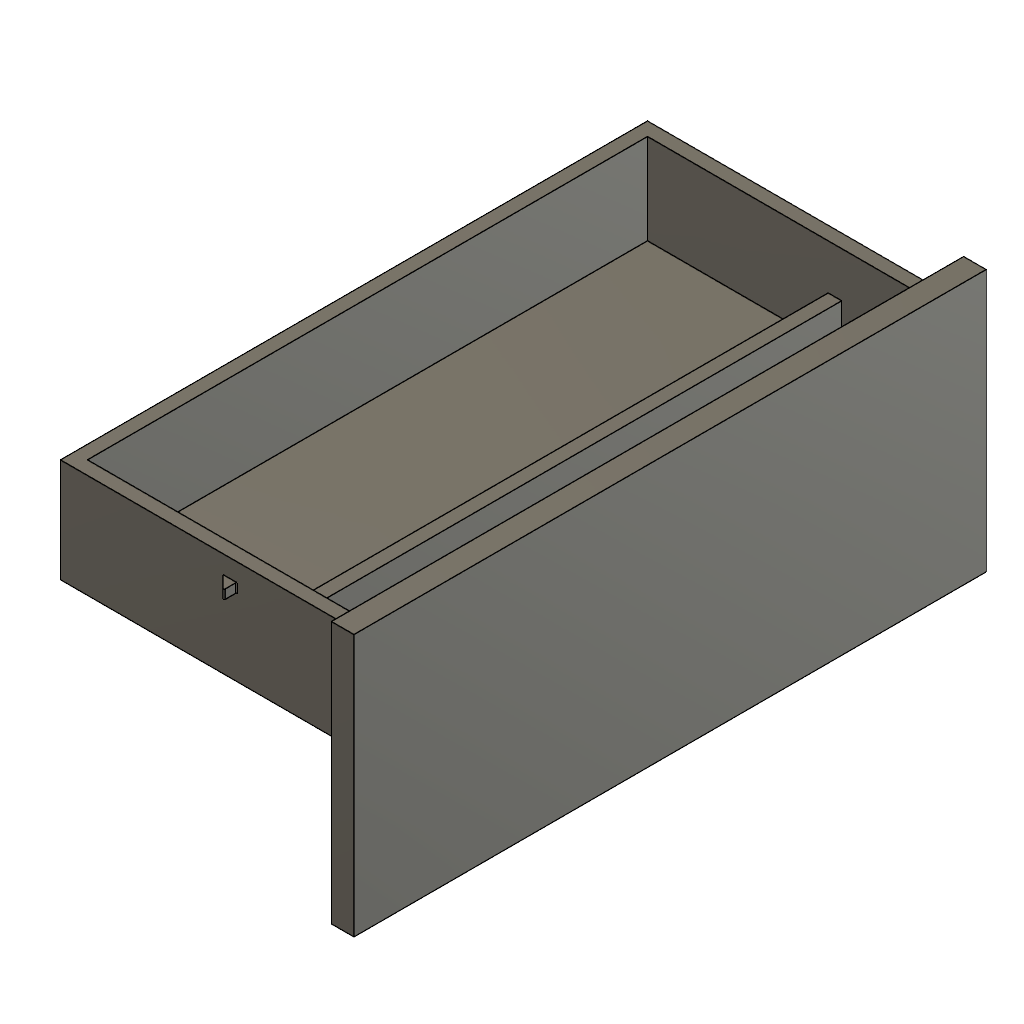
BALANCIN_V4 (Autodesk Fusion 360 archive; units mm, degrees)
design "CAJA BATERIA"
part number: 2026-09-12-01-05-41-271
Autodesk Fusion 360 part; units mm, degrees
sketch "Boceto9" plane through (0, 0, 0) normal (1, 0, 0) x (0, 0, -1)
  line L0 (0, 0) -> (130, 0)
  line L1 (130, 0) -> (130, 3)
  line L2 (130, 3) -> (0, 3)
  line L3 (0, 3) -> (0, 0)
  dimension "d48" = 130
  dimension "d49" = 3
  constraint horizontal L0
  constraint vertical L1
  constraint horizontal L2
  constraint vertical L3
  constraint coincident L0.start L3.end
  measures "d48" distance of L0.start L0.end
  measures "d49" distance of L0.start L2.end
extrude "Extruir9" add sketch "Boceto9" against normal blind 65
sketch "Boceto11" plane through (0, 3, 0) normal (0, 1, 0) x (-1, 0, 0)
  line L0 (0, -130) -> (65, -130)
  line L1 (65, -130) -> (65, 0)
  line L2 (65, 0) -> (0, 0)
  line L3 (0, -130) -> (65, -130)
  line L4 (65, -130) -> (65, -127)
  line L5 (65, -127) -> (0, -127)
  line L6 (0, -127) -> (0, -130)
  line L7 (65, -130) -> (62, -130)
  line L8 (62, -130) -> (62, 0)
  line L9 (62, 0) -> (65, 0)
  line L10 (65, 0) -> (65, -130)
  line L11 (0, 0) -> (65, 0)
  line L12 (65, 0) -> (65, -3)
  line L13 (65, -3) -> (0, -3)
  line L14 (0, -3) -> (0, 0)
  line L15 (0, 0) -> (0, -130)
  line L16 (0, 0) -> (-5, 0)
  line L17 (-5, 0) -> (-5, -3)
  line L18 (-5, -3) -> (0, -3)
  line L19 (0, -3) -> (0, 0)
  line L20 (0, -130) -> (-5, -130)
  line L21 (-5, -130) -> (-5, -127)
  line L22 (-5, -127) -> (0, -127)
  line L23 (0, -127) -> (0, -130)
  dimension "d59" = 3
  dimension "d60" = 3
  dimension "d61" = 3
  dimension "d93" = 5
  dimension "d94" = 3
  dimension "d95" = 5
  dimension "d96" = 3
  constraint horizontal L3
  constraint vertical L4
  constraint horizontal L5
  constraint vertical L6
  constraint coincident L0.start L3.start
  constraint horizontal L7
  constraint vertical L8
  constraint horizontal L9
  constraint vertical L10
  constraint horizontal L11
  constraint vertical L12
  constraint horizontal L13
  constraint vertical L14
  constraint coincident L2.end L11.start
  constraint horizontal L16
  constraint vertical L17
  constraint horizontal L18
  constraint vertical L19
  constraint horizontal L20
  constraint vertical L21
  constraint horizontal L22
  constraint vertical L23
  measures "d59" distance of L0.start L5.end
  measures "d60" distance of L0.end L7.end
  measures "d61" distance of L2.end L13.end
  measures "d93" distance of L2.end L16.end
  measures "d94" distance of L2.end L13.end
  measures "d95" distance of L0.start L20.end
  measures "d96" distance of L0.start L5.end
extrude "Extruir11" add sketch "Boceto11" along normal blind 20 contours L0 L3 L5 L6 L8 L15 L23 | L6 L15 L20 L21 L22 L23 | L0 L1 L3 L4 L5 L7 L8 L10 | L1 L5 L8 L10 L13 | L2 L8 L11 L13 L14 L15 L19 | L14 L15 L16 L17 L18 L19 | L1 L2 L8 L9 L10 L11 L12 L13
sketch "Boceto12" plane through (0, 3, 0) normal (0, 1, 0) x (-1, 0, 0)
  line L0 (62, -3) -> (0, -3)
  line L1 (0, -127) -> (62, -127)
  line L2 (62, -127) -> (62, -3)
  line L3 (62, -127) -> (22, -127)
  line L4 (22, -127) -> (19, -127)
  line L5 (19, -127) -> (19, -7)
  line L6 (19, -7) -> (22, -7)
  line L7 (22, -7) -> (22, -127)
  line L8 (19, -7) -> (39, -7)
  line L9 (39, -7) -> (39, -3)
  line L10 (39, -3) -> (19, -3)
  line L11 (19, -3) -> (19, -7)
  line L12 (0, -3) -> (0, -127)
  dimension "d68" = 40
  dimension "d69" = 3
  dimension "d70" = 120
  dimension "d71" = 20
  constraint coincident L1.end L2.start
  constraint perpendicular L2 L3
  constraint horizontal L4
  constraint vertical L5
  constraint horizontal L6
  constraint vertical L7
  constraint horizontal L8
  constraint vertical L9
  constraint horizontal L10
  constraint vertical L11
  measures "d68" distance of L1.end L3.end
  measures "d69" distance of L3.end L4.end
  measures "d70" distance of L3.end L6.end
  measures "d71" distance of L5.end L8.end
extrude "Extruir12" add sketch "Boceto12" along normal blind 10 contours L0 L6 L8 L9 L10 L11 | L1 L4 L5 L6 L7 L8
sketch "Boceto13" plane through (0, 23, 0) normal (0, 1, 0) x (-1, 0, 0)
  line L0 (62, -127) -> (-5, -127)
  line L1 (-5, -130) -> (65, -130)
  line L2 (65, -130) -> (65, 0)
  line L3 (65, 0) -> (-5, 0)
  line L4 (-5, -3) -> (62, -3)
  line L5 (62, -3) -> (62, -127)
  line L6 (-5, 0) -> (25.8, 0)
  line L7 (-5, -130) -> (25.8, -130)
  line L8 (26, 0.2) -> (26, 2.5172)
  line L9 (26, 0) -> (29, 0)
  line L10 (29, 0) -> (26.3414, 2.6586)
  arc A0 (26.3414, 2.6586) -> (26, 2.5172) centre (26.2, 2.5172) ccw
  arc A1 (25.8, 0) -> (26, 0.2) centre (25.8, 0.2) ccw
  line L11 (26, -130.2) -> (26, -132.5172)
  line L12 (26, -130) -> (29, -130)
  line L13 (29, -130) -> (26.3414, -132.6586)
  arc A2 (26, -132.5172) -> (26.3414, -132.6586) centre (26.2, -132.5172) ccw
  arc A3 (26, -130.2) -> (25.8, -130) centre (25.8, -130.2) ccw
  line L14 (-5, 0) -> (-5, -3)
  line L15 (-5, -127) -> (-5, -130)
  point P0 (26, 3)
  point P1 (26, -133)
  dimension "d85" = 31
  dimension "d86" = 3
  dimension "d87" = 3
  dimension "d88" = 0.2
  dimension "d89" = 31
  dimension "d90" = 3
  dimension "d91" = 3
  dimension "d92" = 0.2
  constraint coincident L3.end L6.start
  constraint coincident L1.start L7.start
  constraint perpendicular L3 L8
  constraint perpendicular L8 L9
  constraint coincident P0 L8
  constraint coincident P0 L10
  constraint tangent L8 A0
  constraint tangent L10 A0
  constraint coincident L6 L9.start
  constraint coincident L9.start L8
  constraint tangent L6 A1
  constraint tangent L8 A1
  constraint equal A0 A1
  constraint perpendicular L7 L11
  constraint perpendicular L11 L12
  constraint coincident P1 L11
  constraint coincident P1 L13
  constraint tangent L11 A2
  constraint tangent L13 A2
  constraint coincident L7 L12.start
  constraint coincident L12.start L11
  constraint tangent L7 A3
  constraint tangent L11 A3
  constraint equal A2 A3
  measures "d85" distance of L3.end L9.start
  measures "d86" distance of L9.start P0
  measures "d87" distance of L9.start L9.end
  measures "d88" radius of A0
  measures "d89" distance of L1.start L12.start
  measures "d90" distance of L12.start P1
  measures "d91" distance of L12.start L12.end
  measures "d92" radius of A2
extrude "Extruir13" add sketch "Boceto13" against normal blind 2 from surface at -4
sketch "Boceto10" plane through (0, 0, 0) normal (1, 0, 0) x (0, 0, -1)
  line L0 (0, 0) -> (-5, 0)
  line L1 (-5, 0) -> (-5, 27)
  line L2 (-5, 27) -> (135, 27)
  line L3 (135, 27) -> (135, -31)
  line L4 (135, -31) -> (-5, -31)
  line L5 (-5, -31) -> (-5, 27)
  line L6 (0, 0) -> (0, 3)
  line L7 (0, 3) -> (3, 3)
  line L8 (3, 3) -> (3, 23)
  line L9 (3, 23) -> (0, 23)
  line L10 (0, 23) -> (0, 3)
  line L11 (130, 3) -> (127, 3)
  line L12 (127, 3) -> (127, 23)
  line L13 (127, 23) -> (130, 23)
  line L14 (130, 23) -> (130, 3)
  dimension "d64" = 5
  dimension "d65" = 27
  dimension "d66" = 140
  dimension "d67" = 58
  dimension "d97" = 3
  dimension "d98" = 20
  constraint coincident L0.start L6.start
  constraint horizontal L0
  constraint perpendicular L0 L1
  constraint horizontal L2
  constraint vertical L3
  constraint horizontal L4
  constraint vertical L5
  constraint perpendicular L0 L6
  constraint horizontal L7
  constraint vertical L8
  constraint horizontal L9
  constraint vertical L10
  constraint horizontal L11
  constraint vertical L12
  constraint horizontal L13
  constraint vertical L14
  measures "d64" distance of L0.start L0.end
  measures "d65" distance of L0.end L1.end
  measures "d66" distance of L1.end L2.end
  measures "d67" distance of L1.end L4.end
  measures "d97" distance of L11.start L11.end
  measures "d98" distance of L11.start L13.end
extrude "Extruir14" add sketch "Boceto10" along normal blind 5

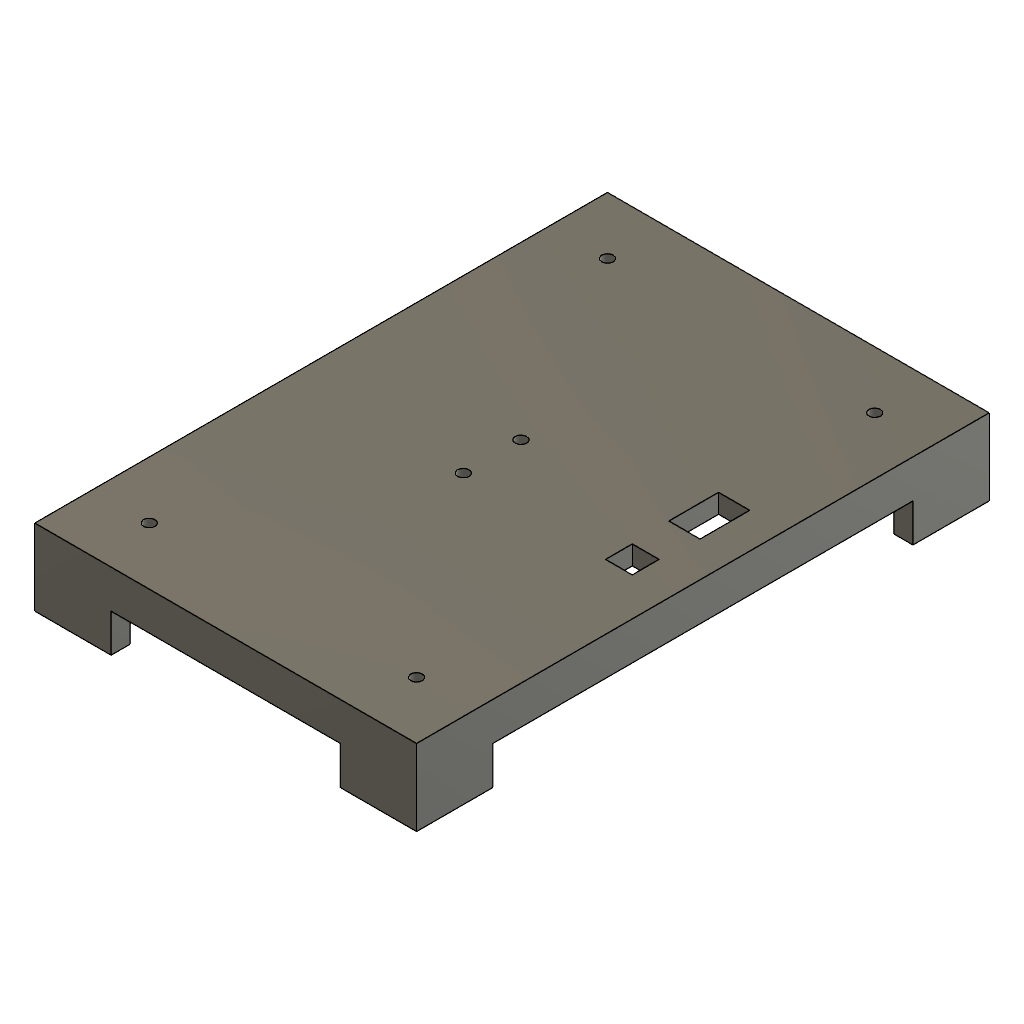
design "TAPA"
part number: 2026-09-12-01-46-28-572
Autodesk Fusion 360 part; units mm, degrees
sketch "Boceto11" plane through (0, 0, 0) normal (0, 1, 0) x (1, 0, 0)
  line L0 (0, 0) -> (100, 0)
  line L1 (100, 0) -> (100, -150)
  line L2 (100, -150) -> (0, -150)
  line L3 (0, -150) -> (0, 0)
  dimension "d80" = 100
  dimension "d81" = 150
  constraint horizontal L0
  constraint vertical L1
  constraint horizontal L2
  constraint vertical L3
  constraint coincident L0.start L3.end
  measures "d80" distance of L0.start L0.end
  measures "d81" distance of L0.start L2.end
extrude "Extruir1" add sketch "Boceto11" along normal blind 5 from surface at 15
sketch "Boceto3" plane through (0, 15, 0) normal (0, -1, 0) x (1, 0, 0)
  line L0 (0, 0) -> (100, 0)
  line L1 (100, 0) -> (100, 5)
  line L2 (100, 5) -> (0, 5)
  line L3 (0, 5) -> (0, 0)
  line L4 (100, 0) -> (95, 0)
  line L5 (95, 0) -> (95, 150)
  line L6 (95, 150) -> (100, 150)
  line L7 (100, 150) -> (100, 0)
  line L8 (100, 150) -> (0, 150)
  line L9 (0, 150) -> (0, 145)
  line L10 (0, 145) -> (100, 145)
  line L11 (100, 145) -> (100, 150)
  line L12 (0, 150) -> (5, 150)
  line L13 (5, 150) -> (5, 0)
  line L14 (5, 0) -> (0, 0)
  line L15 (0, 0) -> (0, 150)
  dimension "d155" = 5
  dimension "d156" = 5
  dimension "d157" = 150
  dimension "d158" = 100
  dimension "d159" = 5
  dimension "d160" = 5
  dimension "d161" = 150
  constraint horizontal L0
  constraint vertical L1
  constraint horizontal L2
  constraint vertical L3
  constraint coincident L0.start L3.end
  constraint horizontal L4
  constraint vertical L5
  constraint horizontal L6
  constraint vertical L7
  constraint horizontal L8
  constraint vertical L9
  constraint horizontal L10
  constraint vertical L11
  constraint horizontal L12
  constraint vertical L13
  constraint horizontal L14
  constraint vertical L15
  measures "d155" distance of L0.start L2.end
  measures "d156" distance of L0.end L4.end
  measures "d157" distance of L0.end L6.end
  measures "d158" distance of L6.end L8.end
  measures "d159" distance of L6.end L10.end
  measures "d160" distance of L8.end L12.end
  measures "d161" distance of L8.end L0.start
extrude "Extruir2" add sketch "Boceto3" along normal blind 15 contours L0 L2 L3 L13 L14 L15 | L0 L2 L5 L13 | L2 L10 L13 L15 | L0 L1 L2 L4 L5 L7 | L8 L9 L10 L12 L13 L15 | L2 L5 L7 L10 | L5 L8 L10 L13 | L5 L6 L7 L8 L10 L11
sketch "Boceto14" plane through (0, 20, 0) normal (0, 1, 0) x (-1, 0, 0)
  line L0 (0, 150) -> (-100, 150)
  line L1 (-100, 150) -> (-100, 0)
  line L2 (-100, 0) -> (0, 0)
  line L3 (0, 0) -> (0, 150)
  line L4 (-100, 150) -> (-100, 80)
  line L5 (-100, 80) -> (-90, 80)
  line L6 (-90, 80) -> (-90, 76.5)
  line L7 (-90, 76.5) -> (-83, 76.5)
  line L8 (-83, 76.5) -> (-83, 83.5)
  line L9 (-83, 83.5) -> (-90, 83.5)
  line L10 (-90, 83.5) -> (-90, 76.5)
  line L11 (-86.5, 76.5) -> (-86.5, 66.5)
  line L12 (-86.5, 66.5) -> (-100, 66.5)
  line L13 (-86.5, 66.5) -> (-82.5879, 66.5)
  line L14 (-82.5879, 66.5) -> (-90.7379, 66.5)
  line L15 (-90.7379, 66.5) -> (-90.7379, 53.5)
  line L16 (-90.7379, 53.5) -> (-82.5879, 53.5)
  line L17 (-82.5879, 53.5) -> (-82.5879, 66.5)
  dimension "d106" = 70
  dimension "d107" = 10
  dimension "d108" = 3.5
  dimension "d109" = 7
  dimension "d110" = 7
  dimension "d122" = 10
  dimension "d123" = 8.15
  dimension "d124" = 13
  constraint coincident L0.end L1.start
  constraint perpendicular L0 L4
  constraint perpendicular L4 L5
  constraint perpendicular L5 L6
  constraint horizontal L7
  constraint vertical L8
  constraint horizontal L9
  constraint vertical L10
  constraint midpoint L7 L11.start
  constraint perpendicular L7 L11
  constraint coincident L1 L12.end
  constraint perpendicular L1 L12
  constraint perpendicular L11 L13
  constraint horizontal L14
  constraint vertical L15
  constraint horizontal L16
  constraint vertical L17
  measures "d106" distance of L0.end L4.end
  measures "d107" distance of L4.end L5.end
  measures "d108" distance of L5.end L6.end
  measures "d109" distance of L6.end L7.end
  measures "d110" distance of L6.end L9.end
  measures "d122" distance of L11.start L11.end
  measures "d123" distance of L13.end L14.end
  measures "d124" distance of L13.end L16.end
extrude "Extruir9" cut sketch "Boceto14" against normal blind 30 contours L6 L7 L8 L9 L10 | L12 L13 L14 L15 L16 L17
sketch "Boceto15" plane through (0, 0, 150) normal (0, 0, 1) x (1, 0, 0)
  line L0 (100, 0) -> (100, 20)
  line L1 (100, 20) -> (0, 20)
  line L2 (0, 20) -> (0, 0)
  line L3 (0, 0) -> (100, 0)
  line L4 (0, 0) -> (20, 0)
  line L5 (100, 0) -> (80, 0)
  line L6 (80, 0) -> (20, 0)
  line L7 (20, 0) -> (20, 10)
  line L8 (20, 10) -> (80, 10)
  line L9 (80, 10) -> (80, 0)
  dimension "d113" = 20
  dimension "d114" = 20
  dimension "d115" = 10
  constraint coincident L2.end L3.start
  constraint perpendicular L2 L4
  constraint coincident L0.start L3.end
  constraint perpendicular L0 L5
  constraint horizontal L6
  constraint vertical L7
  constraint horizontal L8
  constraint vertical L9
  measures "d113" distance of L2.end L4.end
  measures "d114" distance of L0.start L5.end
  measures "d115" distance of L5.end L8.end
extrude "Extruir10" cut sketch "Boceto15" against normal blind 180 contours L3 L6 L7 L8 L9
sketch "Boceto16" plane through (100, 0, 0) normal (1, 0, 0) x (0, 0, -1)
  line L0 (0, 0) -> (0, 20)
  line L1 (0, 20) -> (-150, 20)
  line L2 (-150, 20) -> (-150, 0)
  line L3 (-150, 0) -> (0, 0)
  line L4 (0, 0) -> (-20, 0)
  line L5 (-150, 0) -> (-130, 0)
  line L6 (-130, 0) -> (-20, 0)
  line L7 (-20, 0) -> (-20, 10)
  line L8 (-20, 10) -> (-130, 10)
  line L9 (-130, 10) -> (-130, 0)
  dimension "d118" = 20
  dimension "d119" = 20
  constraint coincident L0.start L3.end
  constraint perpendicular L0 L4
  constraint coincident L2.end L3.start
  constraint perpendicular L2 L5
  constraint horizontal L6
  constraint vertical L7
  constraint horizontal L8
  constraint vertical L9
  measures "d118" distance of L0.start L4.end
  measures "d119" distance of L2.end L5.end
extrude "Extruir11" cut sketch "Boceto16" against normal blind 130 contours L3 L6 L7 L8 L9
sketch "Boceto17" plane through (0, 20, 0) normal (0, 1, 0) x (-1, 0, 0)
  line L0 (-83, 76.5) -> (-90, 76.5)
  line L1 (-90, 76.5) -> (-90, 83.5)
  line L2 (-90, 83.5) -> (-83, 83.5)
  line L3 (-83, 83.5) -> (-83, 76.5)
  line L4 (-90.7379, 66.5) -> (-82.5879, 66.5)
  line L5 (-82.5879, 66.5) -> (-82.5879, 53.5)
  line L6 (-82.5879, 53.5) -> (-90.7379, 53.5)
  line L7 (-90.7379, 53.5) -> (-90.7379, 66.5)
  line L8 (0, 150) -> (-100, 150)
  line L9 (-100, 150) -> (-100, 0)
  line L10 (-100, 0) -> (0, 0)
  line L11 (0, 0) -> (0, 150)
  line L12 (-100, 0) -> (-85, 0)
  line L13 (-85, 0) -> (-85, 15)
  circle A0 centre (-85, 15) radius 1.5
  line L14 (0, 0) -> (-15, 0)
  line L15 (-15, 0) -> (-15, 15)
  circle A1 centre (-15, 15) radius 1.5
  line L16 (0, 150) -> (-15, 150)
  line L17 (-15, 150) -> (-15, 135)
  circle A2 centre (-15, 135) radius 1.5
  line L18 (-100, 150) -> (-85, 150)
  line L19 (-85, 150) -> (-85, 135)
  circle A3 centre (-85, 135) radius 1.5
  dimension "d125" = 15
  dimension "d126" = 15
  dimension "d127" = 3
  dimension "d128" = 15
  dimension "d129" = 15
  dimension "d130" = 3
  dimension "d131" = 15
  dimension "d132" = 15
  dimension "d133" = 3
  dimension "d134" = 15
  dimension "d135" = 15
  dimension "d136" = 3
  constraint coincident L9.end L10.start
  constraint perpendicular L9 L12
  constraint perpendicular L10 L13
  constraint coincident L13.end A0.centre
  constraint coincident L10.end L11.start
  constraint perpendicular L11 L14
  constraint perpendicular L10 L15
  constraint coincident L15.end A1.centre
  constraint coincident L8.start L11.end
  constraint perpendicular L11 L16
  constraint perpendicular L8 L17
  constraint coincident L17.end A2.centre
  constraint coincident L8.end L9.start
  constraint perpendicular L9 L18
  constraint perpendicular L8 L19
  constraint coincident L19.end A3.centre
  measures "d125" distance of L9.end L12.end
  measures "d126" distance of L12.end L13.end
  measures "d127" diameter of A0
  measures "d128" distance of L10.end L14.end
  measures "d129" distance of L14.end L15.end
  measures "d130" diameter of A1
  measures "d131" distance of L8.start L16.end
  measures "d132" distance of L16.end L17.end
  measures "d133" diameter of A2
  measures "d134" distance of L8.end L18.end
  measures "d135" distance of L18.end L19.end
  measures "d136" diameter of A3
extrude "Extruir12" cut sketch "Boceto17" against normal blind 20 contours A0 | A1 | A2 | A3
sketch "Boceto18" plane through (0, 15, 0) normal (0, -1, 0) x (1, 0, 0)
  line L0 (95, 140) -> (95, 10)
  line L1 (95, 140) -> (95, 75)
  line L2 (95, 75) -> (50, 75)
  line L3 (50, 75) -> (50, 85.35)
  line L4 (50, 85.35) -> (42, 85.35)
  line L5 (42, 85.35) -> (58, 85.35)
  line L6 (58, 85.35) -> (58, 64.65)
  line L7 (58, 64.65) -> (42, 64.65)
  line L8 (42, 64.65) -> (42, 85.35)
  line L9 (95, 145) -> (5, 145)
  line L10 (5, 145) -> (5, 5)
  line L11 (5, 5) -> (95, 5)
  line L12 (95, 5) -> (95, 145)
  line L13 (82.5879, 66.5) -> (90.7379, 66.5)
  line L14 (90.7379, 66.5) -> (90.7379, 53.5)
  line L15 (90.7379, 53.5) -> (82.5879, 53.5)
  line L16 (82.5879, 53.5) -> (82.5879, 66.5)
  line L17 (90, 76.5) -> (83, 76.5)
  line L18 (83, 76.5) -> (83, 83.5)
  line L19 (83, 83.5) -> (90, 83.5)
  line L20 (90, 83.5) -> (90, 76.5)
  circle A0 centre (15, 135) radius 1.5
  circle A1 centre (15, 15) radius 1.5
  circle A2 centre (85, 135) radius 1.5
  circle A3 centre (85, 15) radius 1.5
  line L21 (100, 0) -> (0, 0)
  dimension "d140" = 45
  dimension "d141" = 10.35
  dimension "d142" = 8
  dimension "d143" = 16
  dimension "d144" = 20.7
  dimension "d162" = 75
  constraint midpoint L0 L1.end
  constraint perpendicular L2 L3
  constraint perpendicular L3 L4
  constraint horizontal L5
  constraint vertical L6
  constraint horizontal L7
  constraint vertical L8
  measures "d140" distance of L1.end L2.end
  measures "d141" distance of L2.end L3.end
  measures "d142" distance of L3.end L4.end
  measures "d143" distance of L4.end L5.end
  measures "d144" distance of L4.end L7.end
  measures "d162" distance of L2 L21
extrude "Extruir13" cut sketch "Boceto18" against normal blind 2 contours L2 L3 L4 L5 L6 L7 L8 | L2 L3 L5 L6
sketch "Boceto19" plane through (0, 17, 0) normal (0, -1, 0) x (1, 0, 0)
  line L0 (42, 64.65) -> (58, 64.65)
  line L1 (58, 64.65) -> (58, 85.35)
  line L2 (58, 85.35) -> (42, 85.35)
  line L3 (42, 85.35) -> (42, 64.65)
  line L4 (42, 64.65) -> (44.8, 64.65)
  line L5 (44.8, 64.65) -> (44.8, 67.45)
  line L6 (44.8, 67.45) -> (42, 67.45)
  line L7 (42, 67.45) -> (42, 64.65)
  line L8 (42, 85.35) -> (44.8, 85.35)
  line L9 (44.8, 85.35) -> (44.8, 82.55)
  line L10 (44.8, 82.55) -> (42, 82.55)
  line L11 (42, 82.55) -> (42, 85.35)
  circle A0 centre (44.8, 82.55) radius 1.5
  circle A1 centre (44.8, 67.45) radius 1.5
  dimension "d147" = 2.8
  dimension "d148" = 2.8
  dimension "d149" = 2.8
  dimension "d150" = 2.8
  dimension "d163" = 20.7
  dimension "d164" = 16
  dimension "d165" = 3
  dimension "d166" = 3
  constraint horizontal L4
  constraint vertical L5
  constraint horizontal L6
  constraint vertical L7
  constraint coincident L0.start L3.end
  constraint horizontal L8
  constraint vertical L9
  constraint horizontal L10
  constraint vertical L11
  constraint coincident L2.end L3.start
  constraint coincident L9.end L10.start
  constraint coincident L5.end L6.start
  measures "d147" distance of L0.start L4.end
  measures "d148" distance of L0.start L6.end
  measures "d149" distance of L2.end L8.end
  measures "d150" distance of L2.end L10.end
  measures "d163" distance of L0 L2
  measures "d164" distance of L1 L3
  measures "d165" diameter of A0
  measures "d166" diameter of A1
extrude "Extruir14" cut sketch "Boceto19" against normal blind 3.5 contours L5 L6 A1 | L5 L6 A1 | L9 L10 A0 | L9 L10 A0

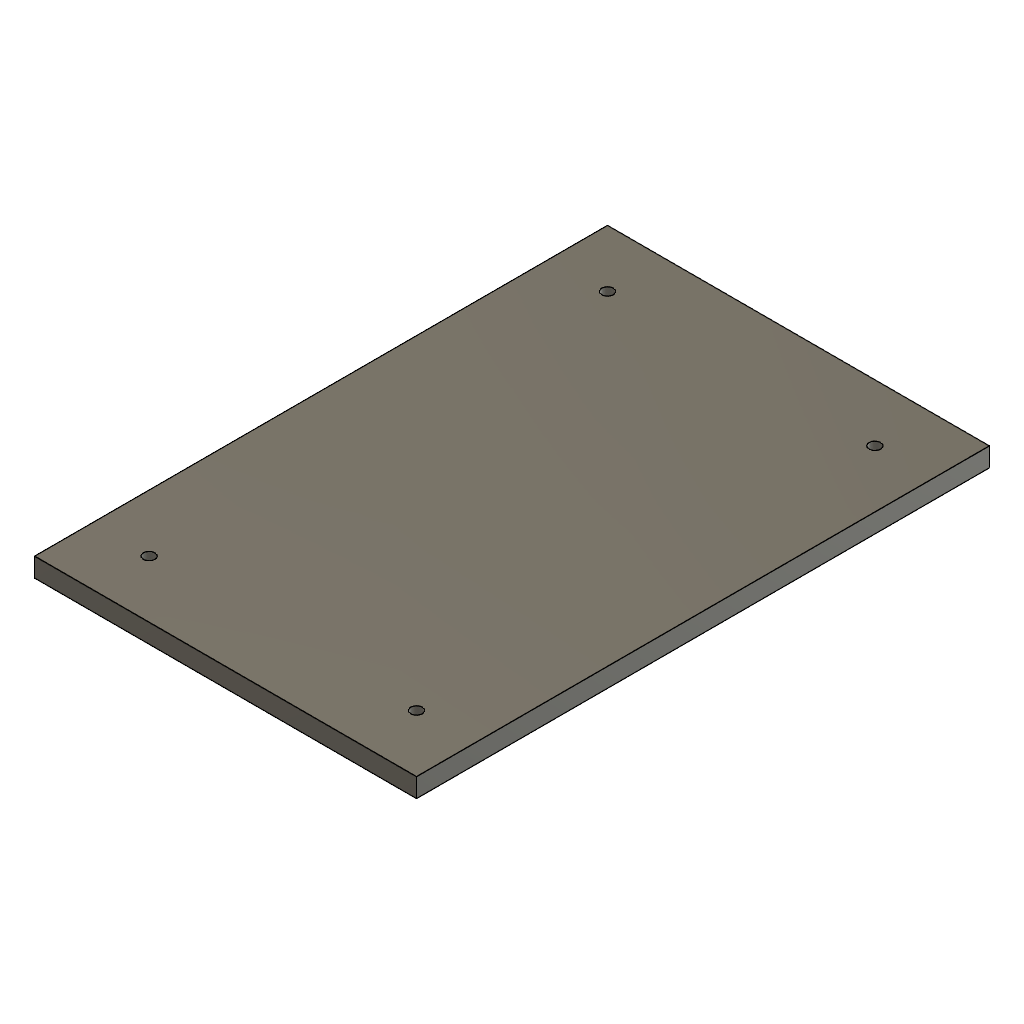
design "PLACA"
part number: 2026-09-12-02-16-54-781
Autodesk Fusion 360 part; units mm, degrees
sketch "Boceto1" plane through (2.5309, 197.6555, 0.0134) normal (0, 1, 0) x (-1, 0, 0)
  line L0 (0, 0) -> (-100, 0)
  line L1 (-100, 0) -> (-100, 150)
  line L2 (-100, 150) -> (0, 150)
  line L3 (0, 150) -> (0, 0)
  line L4 (-100, 150) -> (-85, 150)
  line L5 (-85, 150) -> (-85, 135)
  line L6 (0, 150) -> (-15, 150)
  line L7 (-15, 150) -> (-15, 135)
  line L8 (-100, 0) -> (-85, 0)
  line L9 (-85, 0) -> (-85, 15)
  line L10 (0, 0) -> (-15, 0)
  line L11 (-15, 0) -> (-15, 15)
  circle A0 centre (-15, 15) radius 1.5
  circle A1 centre (-85, 15) radius 1.5
  circle A2 centre (-15, 135) radius 1.5
  circle A3 centre (-85, 135) radius 1.5
  dimension "d3" = 100
  dimension "d4" = 150
  dimension "d5" = 15
  dimension "d6" = 15
  dimension "d7" = 15
  dimension "d8" = 15
  dimension "d9" = 15
  dimension "d10" = 15
  dimension "d11" = 15
  dimension "d12" = 3
  dimension "d13" = 3
  dimension "d14" = 3
  dimension "d15" = 3
  dimension "d16" = 15
  constraint horizontal L0
  constraint vertical L1
  constraint horizontal L2
  constraint vertical L3
  constraint coincident L0.start L3.end
  constraint perpendicular L1 L4
  constraint perpendicular L2 L5
  constraint perpendicular L3 L6
  constraint perpendicular L2 L7
  constraint perpendicular L1 L8
  constraint perpendicular L8 L9
  constraint coincident L0 L10.end
  constraint perpendicular L0 L11
  constraint coincident L11.end A0.centre
  constraint coincident L9.end A1.centre
  constraint coincident L7.end A2.centre
  constraint coincident L5.end A3.centre
  measures "d3" distance of L0.start L0.end
  measures "d4" distance of L0.start L2.end
  measures "d5" distance of L1.end L4.end
  measures "d6" distance of L4.end L5.end
  measures "d7" distance of L2.end L6.end
  measures "d8" distance of L6.end L7.end
  measures "d9" distance of L0.end L8.end
  measures "d10" distance of L8.end L9.end
  measures "d11" distance of L0.start L10.end
  measures "d12" diameter of A0
  measures "d13" diameter of A1
  measures "d14" diameter of A2
  measures "d15" diameter of A3
  measures "d16" distance of L10.end L11.end
extrude "Extruir1" add sketch "Boceto1" along normal blind 5

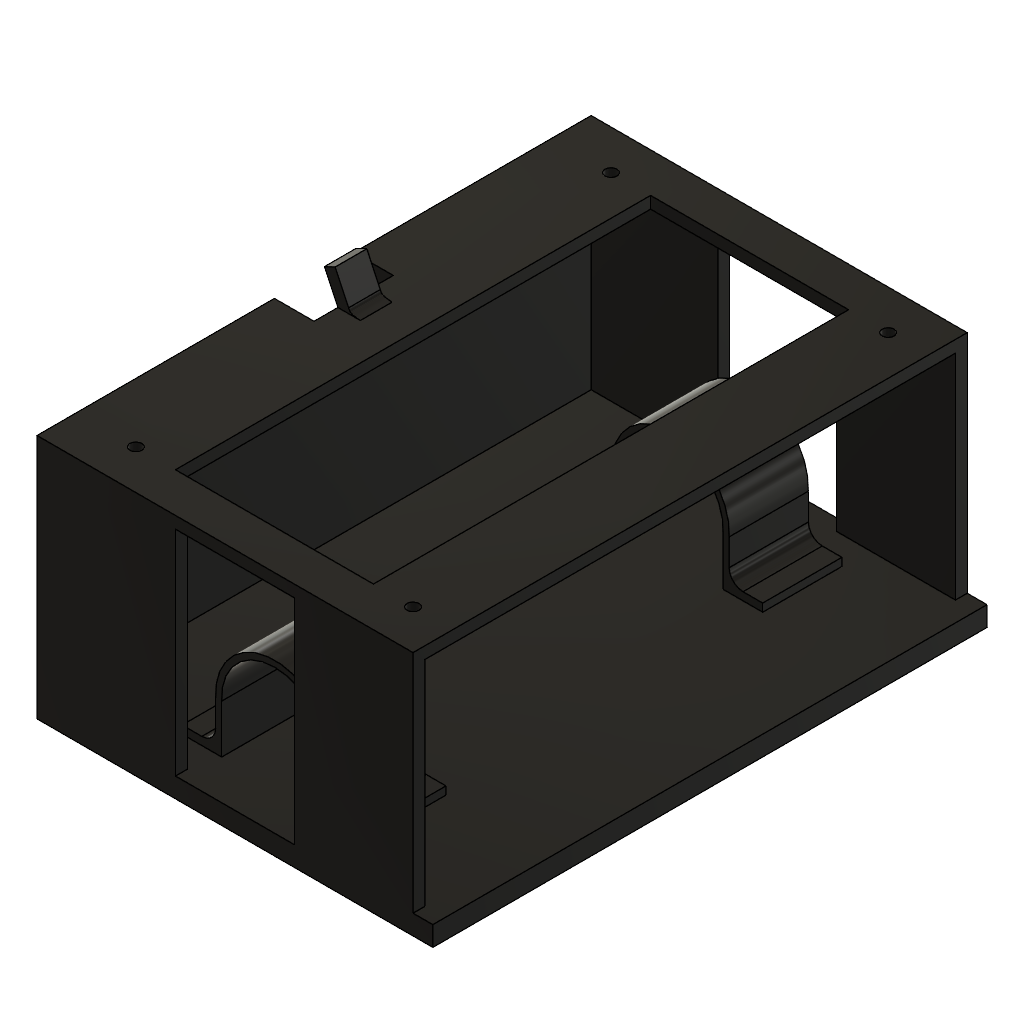
design "BASE"
part number: 2026-09-12-00-28-25-812
Autodesk Fusion 360 part; units mm, degrees
derive "DerivedContext1"
sketch "Boceto3" plane through (0, 0, 0) normal (1, 0, 0) x (0, 0, -1)
  line L0 (0, 0) -> (0, 20)
  line L1 (0, 20) -> (-70, 20)
  line L2 (0, 20) -> (70, 20)
  line L3 (-70, 20) -> (70, 20)
  line L4 (70, 20) -> (70, 15)
  line L5 (70, 15) -> (-70, 15)
  line L6 (-70, 15) -> (-70, 20)
  dimension "d3" = 5
  dimension "d17" = 20
  dimension "d75" = 70
  dimension "d76" = 70
  constraint coincident L0.start origin
  constraint perpendicular L0 L1
  constraint perpendicular L0 L2
  constraint horizontal L3
  constraint vertical L4
  constraint horizontal L5
  constraint vertical L6
  measures "d3" distance of L1.end L5.end
  measures "d17" distance of L0.start L0.end
  measures "d75" distance of L0 L4
  measures "d76" distance of L0 L6
extrude "Extruir1" add sketch "Boceto3" along normal mid plane 100
sketch "Boceto4" plane through (0, 20, 0) normal (0, 1, 0) x (-1, 0, 0)
  line L0 (50, -70) -> (-50, -70)
  line L1 (-50, -70) -> (-50, -67)
  line L2 (-50, -67) -> (50, -67)
  line L3 (50, -67) -> (50, -70)
  line L4 (0, -67) -> (-15, -67)
  line L5 (-15, -67) -> (-15, -70)
  line L6 (-15, -70) -> (0, -70)
  line L7 (0, -67) -> (15, -67)
  line L8 (15, -67) -> (15, -70)
  line L9 (15, -70) -> (0, -70)
  line L10 (-50, -70) -> (-45, -70)
  line L11 (-45, -70) -> (-45, -67)
  line L12 (-45, -67) -> (-50, -67)
  line L13 (-50, -67) -> (-50, -70)
  line L14 (50, -70) -> (47, -70)
  line L15 (47, -70) -> (47, 70)
  line L16 (47, 70) -> (50, 70)
  line L17 (50, 70) -> (50, -70)
  line L18 (50, 70) -> (-50, 70)
  line L19 (-50, 70) -> (-50, 67)
  line L20 (-50, 67) -> (50, 67)
  line L21 (50, 67) -> (50, 70)
  line L22 (-50, 70) -> (-45, 70)
  line L23 (-45, 70) -> (-45, 67)
  line L24 (-45, 67) -> (-50, 67)
  line L25 (-50, 67) -> (-50, 70)
  line L26 (0, 70) -> (15, 70)
  line L27 (15, 70) -> (15, 67)
  line L28 (15, 67) -> (0, 67)
  line L29 (0, 67) -> (0, 70)
  line L30 (0, 70) -> (-15, 70)
  line L31 (-15, 70) -> (-15, 67)
  line L32 (-15, 67) -> (0, 67)
  line L33 (0, 67) -> (0, 70)
  dimension "d85" = 15
  dimension "d86" = 3
  dimension "d87" = 15
  dimension "d88" = 3
  dimension "d97" = 5
  dimension "d116" = 3
  dimension "d119" = 3
  dimension "d120" = 140
  dimension "d121" = 100
  dimension "d122" = 5
  dimension "d123" = 3
  dimension "d124" = 3
  dimension "d126" = 15
  dimension "d127" = 3
  dimension "d128" = 15
  dimension "d129" = 3
  constraint horizontal L0
  constraint vertical L1
  constraint horizontal L2
  constraint vertical L3
  constraint horizontal L4
  constraint vertical L5
  constraint horizontal L6
  constraint midpoint L2 L4.start
  constraint horizontal L7
  constraint vertical L8
  constraint horizontal L9
  constraint horizontal L10
  constraint vertical L11
  constraint horizontal L12
  constraint vertical L13
  constraint horizontal L14
  constraint vertical L15
  constraint horizontal L16
  constraint vertical L17
  constraint horizontal L18
  constraint vertical L19
  constraint horizontal L20
  constraint vertical L21
  constraint horizontal L22
  constraint vertical L23
  constraint horizontal L24
  constraint vertical L25
  constraint horizontal L26
  constraint vertical L27
  constraint horizontal L28
  constraint vertical L29
  constraint midpoint L18 L26.start
  constraint horizontal L30
  constraint vertical L31
  constraint horizontal L32
  constraint vertical L33
  measures "d85" distance of L4.start L4.end
  measures "d86" distance of L4.start L6.end
  measures "d87" distance of L4.start L7.end
  measures "d88" distance of L4.start L6.end
  measures "d97" distance of L0.end L10.end
  measures "d116" distance of L0 L2
  measures "d119" distance of L0.start L14.end
  measures "d120" distance of L0.start L16.end
  measures "d121" distance of L16.end L18.end
  measures "d122" distance of L18.end L22.end
  measures "d123" distance of L18.end L19.end
  measures "d124" distance of L10 L12
  measures "d126" distance of L26.start L26.end
  measures "d127" distance of L26.start L28.end
  measures "d128" distance of L26.start L30.end
  measures "d129" distance of L26.start L28.end
extrude "Extruir2" add sketch "Boceto4" along normal blind 54 contours L0 L2 L3 L14 L15 L17 | L0 L2 L8 L15 | L2 L15 L17 L20 | L15 L16 L17 L18 L20 L21 | L15 L18 L20 L27 | L0 L2 L5 L11 | L18 L20 L23 L31
sketch "Boceto6" plane through (0, 74, 0) normal (0, 1, 0) x (-1, 0, 0)
  line L0 (50, -70) -> (25, -70)
  line L1 (25, -70) -> (25, 70)
  line L2 (25, 70) -> (50, 70)
  line L3 (50, 70) -> (50, -70)
  line L4 (25, -70) -> (-25, -70)
  line L5 (-25, -70) -> (-25, -60)
  line L6 (-25, -60) -> (25, -60)
  line L7 (25, -60) -> (25, -70)
  line L8 (-50, -70) -> (-25, -70)
  line L9 (-25, -70) -> (-25, 70)
  line L10 (25, 60) -> (25, 70)
  line L11 (25, 70) -> (-25, 70)
  line L12 (-25, 70) -> (-25, 60)
  line L13 (-25, 60) -> (25, 60)
  line L14 (25, 60) -> (25, 70)
  line L15 (-45, -70) -> (-25, -70)
  line L16 (-25, -70) -> (-25, 70)
  line L17 (-25, 70) -> (-45, 70)
  line L18 (-45, 70) -> (-45, -70)
  dimension "d89" = 25
  dimension "d90" = 50
  dimension "d91" = 10
  dimension "d95" = 25
  dimension "d96" = 10
  constraint horizontal L0
  constraint vertical L1
  constraint horizontal L2
  constraint vertical L3
  constraint horizontal L4
  constraint vertical L5
  constraint horizontal L6
  constraint vertical L7
  constraint horizontal L8
  constraint vertical L9
  constraint vertical L10
  constraint horizontal L11
  constraint vertical L12
  constraint horizontal L13
  constraint vertical L14
  constraint horizontal L15
  constraint vertical L16
  constraint horizontal L17
  constraint vertical L18
  constraint coincident L8 L15.start
  measures "d89" distance of L0.start L0.end
  measures "d90" distance of L0.end L4.end
  measures "d91" distance of L0.end L6.end
  measures "d95" distance of L8.start L4.end
  measures "d96" distance of L1.end L10.start
extrude "Extruir4" add sketch "Boceto6" 1 faces at (-49, 74, -22.3333) along normal blind 3 contours L0 L1 L2 L3 L7 L10 L14 | L1 L4 L5 L6 L7 L9 L16 | L5 L8 L9 L12 L15 L16 L17 L18 | L1 L9 L10 L11 L12 L13 L14 L16
sketch "Boceto8" plane through (0, 0, 0) normal (0, 0, 1) x (1, 0, 0)
  circle A0 centre (0, 33) radius 13.3417
  circle A1 centre (0, 33) radius 14.8661
  line L0 (-14.8465, 32.2379) -> (-14.8465, 25.5)
  line L1 (-13.3199, 32.2379) -> (-13.3199, 20)
  line L2 (14.8465, 32.2379) -> (14.8465, 25.5)
  line L3 (13.3199, 32.2379) -> (13.3199, 20)
  line L4 (13.3199, 20) -> (14.8465, 20)
  line L5 (-14.8465, 20) -> (-13.3199, 20)
  line L6 (-13.3199, 20) -> (-23.3199, 20)
  line L7 (-23.3199, 20) -> (-23.3199, 22)
  line L8 (-23.3199, 22) -> (-18.3465, 22)
  line L9 (-13.3199, 22) -> (-13.3199, 20)
  arc A2 (-18.3465, 22) -> (-14.8465, 25.5) centre (-18.3465, 25.5) ccw
  line L10 (13.3199, 20) -> (23.3199, 20)
  line L11 (23.3199, 20) -> (23.3199, 22)
  line L12 (23.3199, 22) -> (18.3465, 22)
  line L13 (13.3199, 22) -> (13.3199, 20)
  arc A3 (14.8465, 25.5) -> (18.3465, 22) centre (18.3465, 25.5) ccw
  dimension "d42" = 10
  dimension "d43" = 2
  dimension "d44" = 3.5
  dimension "d45" = 10
  dimension "d46" = 2
  dimension "d47" = 3.5
  constraint concentric A0 A1
  constraint coincident A1 L0.start
  constraint vertical L0
  constraint coincident A0 L1.start
  constraint vertical L1
  constraint coincident A1 L2.start
  constraint parallel L1 L2
  constraint coincident A0 L3.start
  constraint parallel L2 L3
  constraint perpendicular L2 L4
  constraint perpendicular L0 L5
  constraint horizontal L6
  constraint vertical L7
  constraint horizontal L8
  constraint vertical L9
  constraint coincident L9.start L8
  constraint coincident L5.start L0
  constraint tangent L8 A2
  constraint tangent L0 A2
  constraint horizontal L10
  constraint vertical L11
  constraint horizontal L12
  constraint vertical L13
  constraint coincident L13.start L12
  constraint coincident L4.end L2
  constraint tangent L12 A3
  constraint tangent L2 A3
  measures "d42" distance of L1.end L6.end
  measures "d43" distance of L1.end L9.start
  measures "d44" radius of A2
  measures "d45" distance of L3.end L10.end
  measures "d46" distance of L3.end L13.start
  measures "d47" radius of A3
extrude "Extruir6" add sketch "Boceto8" along normal blind 20 from surface at 40 contours A0 A1 L1 L3 | A1 L0 L1 L5 L6 L7 L8 L9 A2 | A1 L2 L3 L4 L10 L11 L12 L13 A3 picked at (-14.3123, 33.6022)
extrude "Extruir7" add sketch "Boceto8" along normal blind 20 from surface at -60 contours A0 A1 L1 L3 | A1 L0 L1 L5 L6 L7 L8 L9 A2 | A1 L2 L3 L4 L10 L11 L12 L13 A3 picked at (-14.3123, 33.6022)
sketch "Boceto13" plane through (0, 77, 0) normal (0, 1, 0) x (-1, 0, 0)
  line L0 (-45, -70) -> (50, -70)
  line L1 (50, -70) -> (50, 70)
  line L2 (50, 70) -> (-45, 70)
  line L3 (-45, 70) -> (-45, -70)
  line L4 (-25, -60) -> (-25, 60)
  line L5 (-25, 60) -> (25, 60)
  line L6 (25, 60) -> (25, -60)
  line L7 (25, -60) -> (-25, -60)
  line L8 (50, -70) -> (35, -70)
  line L9 (35, -70) -> (35, -60)
  circle A0 centre (35, -60) radius 1.5
  line L10 (-45, -70) -> (-35, -70)
  line L11 (-35, -70) -> (-35, -60)
  circle A1 centre (-35, -60) radius 1.5
  line L12 (50, 70) -> (35, 70)
  line L13 (35, 70) -> (35, 60)
  circle A2 centre (35, 60) radius 1.5
  line L14 (-45, 70) -> (-35, 70)
  line L15 (-35, 70) -> (-35, 60)
  circle A3 centre (-35, 60) radius 1.5
  dimension "d100" = 15
  dimension "d101" = 10
  dimension "d102" = 3
  dimension "d103" = 10
  dimension "d104" = 10
  dimension "d105" = 3
  dimension "d106" = 15
  dimension "d107" = 10
  dimension "d108" = 3
  dimension "d109" = 10
  dimension "d110" = 10
  dimension "d111" = 3
  constraint coincident L0.end L1.start
  constraint perpendicular L1 L8
  constraint perpendicular L8 L9
  constraint coincident L9.end A0.centre
  constraint coincident L0.start L3.end
  constraint perpendicular L3 L10
  constraint perpendicular L10 L11
  constraint coincident L11.end A1.centre
  constraint coincident L1.end L2.start
  constraint perpendicular L6 L12
  constraint perpendicular L2 L13
  constraint coincident L13.end A2.centre
  constraint coincident L2.end L3.start
  constraint perpendicular L3 L14
  constraint perpendicular L14 L15
  constraint coincident L15.end A3.centre
  measures "d100" distance of L0.end L8.end
  measures "d101" distance of L8.end L9.end
  measures "d102" diameter of A0
  measures "d103" distance of L0.start L10.end
  measures "d104" distance of L10.end L11.end
  measures "d105" diameter of A1
  measures "d106" distance of L1.end L12.end
  measures "d107" distance of L12.end L13.end
  measures "d108" diameter of A2
  measures "d109" distance of L2.end L14.end
  measures "d110" distance of L14.end L15.end
  measures "d111" diameter of A3
extrude "Extruir13" cut sketch "Boceto13" against normal blind 7 contours A0 | A1 | A2 | A3
sketch "Boceto16" plane through (0, 0, 70) normal (0, 0, 1) x (1, 0, 0)
  line L0 (15, 74) -> (15, 20)
  line L1 (15, 20) -> (-15, 20)
  line L2 (-15, 20) -> (-15, 74)
  line L3 (-15, 74) -> (15, 74)
  line L4 (45, 20) -> (45, 77)
  line L5 (45, 77) -> (-50, 77)
  line L6 (-50, 77) -> (-50, 15)
  line L7 (-50, 15) -> (50, 15)
  line L8 (50, 15) -> (50, 20)
  line L9 (50, 20) -> (45, 20)
  line L10 (-50, 77) -> (-40, 77)
  line L11 (-40, 77) -> (-43.3809, 84.2505)
  line L12 (-40, 77) -> (-37, 77) construction
  line L13 (-43.3809, 84.2505) -> (-40.662, 85.5183)
  line L14 (-40, 77) -> (-37.2811, 78.2679)
  line L15 (-40, 77) -> (-42, 77) construction
  line L16 (-37.2811, 78.2679) -> (-40.662, 85.5183)
  spline S0 degree 2 poles (-37.2811, 78.2679) (-36.8232, 77.286) (-34.3, 77) knots 0 0 0 0.344162 0.344162 0.344162 weights 1 3 1
  dimension "d143" = 10
  dimension "d144" = 115
  dimension "d145" = 8
  dimension "d146" = 3
  dimension "d147" = 25
  dimension "d148" = 3
  constraint coincident L5.end L6.start
  constraint perpendicular L6 L10
  constraint horizontal L12
  constraint perpendicular L11 L13
  constraint horizontal L15
  constraint coincident L5 S0.end
  measures "d143" distance of L5.end L10.end
  measures "d144" angle of L11 L12
  measures "d145" distance of L10.end L11.end
  measures "d146" distance of L11.end L13.end
  measures "d147" angle of L14 L15
  measures "d148" distance of L10.end L14.end
sketch "Boceto17" plane through (0, 0, 70) normal (0, 0, 1) x (1, 0, 0)
  line L0 (-40, 77) -> (-50, 55.5549)
  line L1 (-40, 77) -> (-32.7423, 77) construction
  line L2 (-50, 55.5549) -> (-50, 77)
  line L3 (-50, 77) -> (-40, 77)
  line L4 (-50, 55.5549) -> (-50, 55.0549)
  line L5 (-40, 77) -> (-40, 76.5)
  line L6 (-40, 76.5) -> (-50, 55.0549)
  line L7 (-40, 76.5) -> (-39.7668, 77)
  line L8 (-39.7668, 77) -> (-40, 77)
  point P0 (-40, 77)
  dimension "d150" = 115
  dimension "d157" = 10
  dimension "d158" = 0.5
  dimension "d159" = 0.5
  constraint horizontal L1
  constraint coincident P0 L0.start
  constraint perpendicular L2 L3
  constraint parallel L2 L4
  constraint perpendicular L3 L5
  constraint coincident L1 L7.end
  constraint parallel L6 L7
  constraint perpendicular L5 L8
  measures "d150" angle of L0 L1
  measures "d157" distance of P0 L2.end
  measures "d158" distance of L0.end L4.end
  measures "d159" distance of P0 L5.end
extrude "Extruir14" add sketch "Boceto16" along normal blind 8 from surface at -74 contours L5 L14 S0 | L11 L13 L14 L16
extrude "Extruir15" cut sketch "Boceto17" along normal blind 20 from surface at -80 contours L0 L2 L3
extrude "Extruir16" add sketch "Boceto17" along normal blind 20 from surface at -80 contours L0 L4 L5 L6 | L5 L7 L8
sketch "Boceto18" plane through (0, 0, -10) normal (0, 0, 1) x (1, 0, 0)
  line L0 (-47, 74) -> (-41.3989, 74)
  line L1 (-41.3989, 74) -> (-40, 77)
  line L2 (-40, 77) -> (-50, 77)
  line L3 (-47, 74) -> (-41.3989, 74)
  line L4 (-50, 77) -> (-50, 55.5549)
  line L5 (-47, 61.9885) -> (-47, 74)
  line L6 (-41.3989, 74) -> (-47, 74)
  line L7 (-47, 61.9885) -> (-41.3989, 74)
  line L8 (-50, 55.5549) -> (-47, 61.9885)
  constraint coincident L0.start L3.start
  constraint coincident L0.end L1.start
  constraint coincident L5.start L7.start
extrude "Extruir17" add sketch "Boceto18" against normal blind 2 contours L0 L3 L5 L6 L7
sketch "Boceto19" plane through (0, 0, 10) normal (0, 0, -1) x (-1, 0, 0)
  line L0 (41.3989, 74) -> (47, 74)
  line L1 (50, 77) -> (40, 77)
  line L2 (47, 61.9885) -> (50, 55.5549)
  line L3 (47, 74) -> (47, 61.9885)
  line L4 (50, 55.5549) -> (50, 77)
  line L5 (41.3989, 74) -> (47, 74)
  line L6 (47, 61.9885) -> (41.3989, 74)
  line L7 (40, 77) -> (41.3989, 74)
  constraint coincident L0.start L5.start
  constraint coincident L0.end L3.start
  constraint coincident L2.start L3.end
extrude "Extruir18" add sketch "Boceto19" against normal blind 2 contours L0 L3 L5 L6

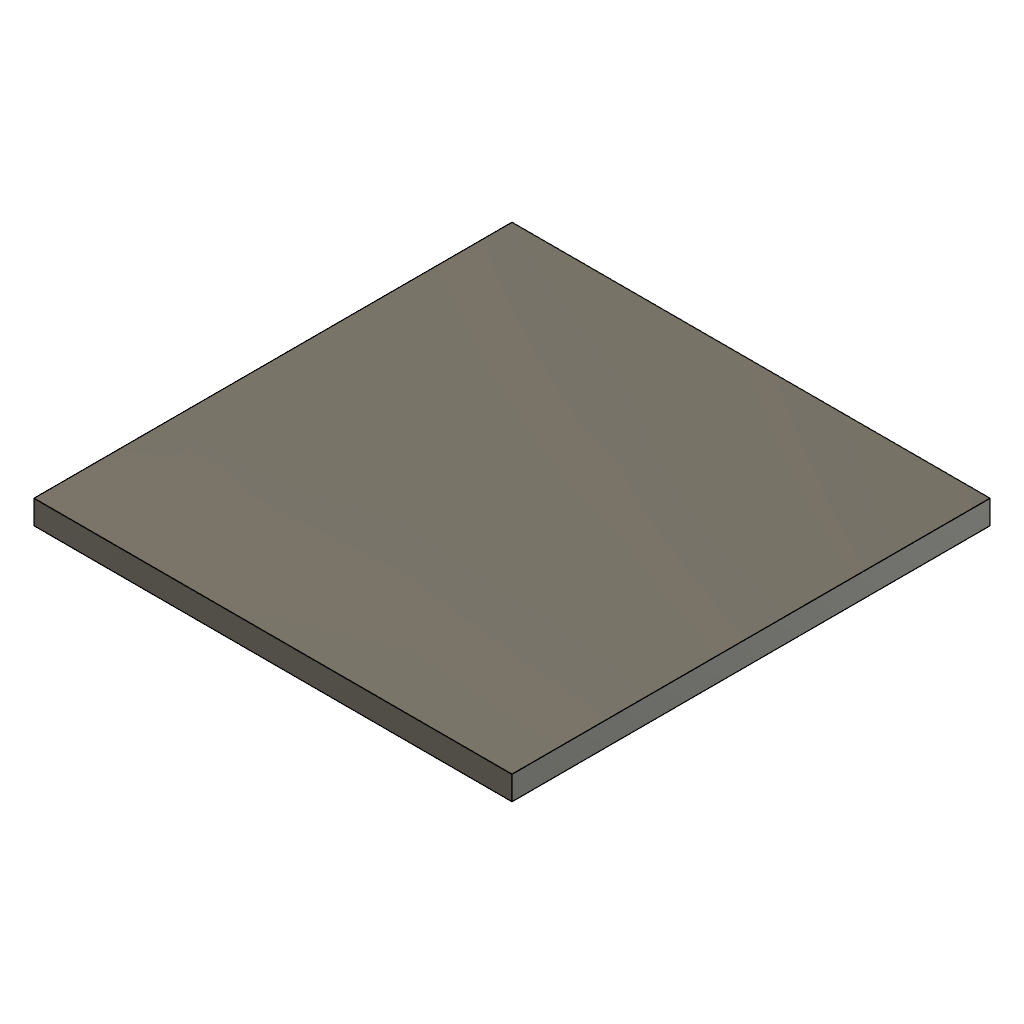
design "SUELO"
part number: 2026-09-16-12-44-53-559
Autodesk Fusion 360 part; units mm, degrees
sketch "Boceto1" plane through (0, 0, 0) normal (0, 1, 0) x (1, 0, 0)
  line L0 (100, 100) -> (-100, 100)
  line L1 (-100, 100) -> (-100, -100)
  line L2 (-100, -100) -> (100, -100)
  line L3 (100, -100) -> (100, 100)
  constraint horizontal L0
  constraint vertical L1
  constraint horizontal L2
  constraint vertical L3
extrude "Extruir1" add sketch "Boceto1" against normal blind 10
